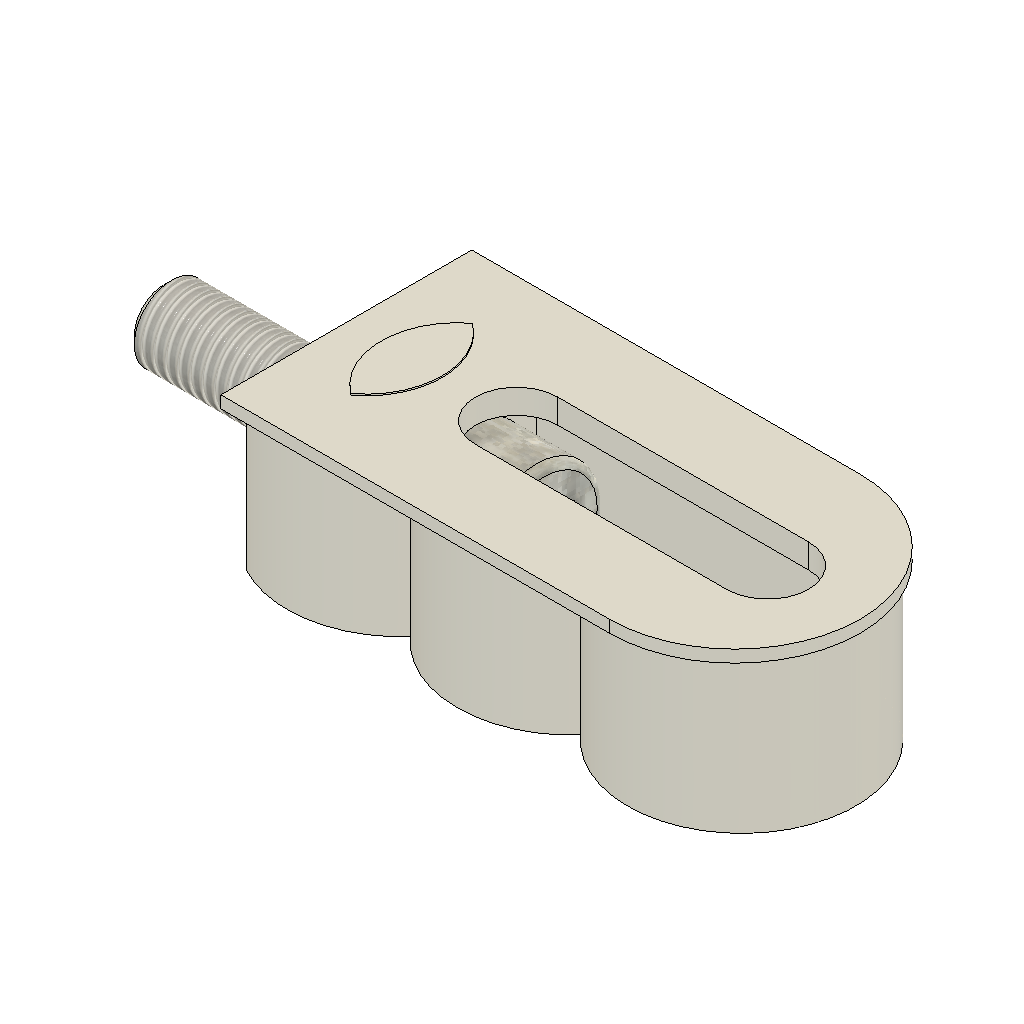
Lamello Cabineo Config (Autodesk Fusion 360 archive; units mm, degrees)
design "Lamello Cabineo Configurable"
description: Lamello Cabineo
part number: Cabineo 12
description: Cap
part number: Lamello Cabineo Cap
description: Lamello Insert
part number: M6 Insert 12.3 mm
Autodesk Fusion 360 part; units mm, degrees
sketch "Sketch1" plane through (0, 0, 0) normal (0, 1, 0) x (1, 0, 0)
  circle A0 centre (14.8, 0) radius 7.5
  circle A1 centre (26, 0) radius 7.5
  line L0 (0, 6.5795) -> (0, -6.5795)
  arc A2 (0, -6.5795) -> (0, 6.5795) centre (3.6, 0) ccw
  dimension "Cabineo_hole_Dia" = 15
  dimension "d9" = 11.2
  dimension "d10" = 11.2
  dimension "d11" = 3.6
  constraint equal A0 A1
  constraint equal A0 A2
  constraint horizontal A2.centre A0.centre
  constraint horizontal A0.centre A1.centre
  constraint vertical L0
  constraint horizontal origin A2.centre
  constraint coincident origin L0
  measures "Cabineo_hole_Dia" diameter of A1
  measures "d9" distance of A0.centre A1.centre
  measures "d10" distance of A2.centre A0.centre
  measures "d11" distance of origin A2.centre
extrude "Extrude1" add sketch "Sketch1" along normal mid plane 10 makes body 1 in component "Lamello Cabineo"
sketch "Sketch1 (2)" plane through (0, 5, 0) normal (0, 1, 0) x (-1, 0, 0) in component "Lamello Cabineo"
  arc A0 (0, 6.5795) -> (-9.2, 4.989) centre (-3.6, 0) ccw
  arc A1 (-9.2, 4.989) -> (-20.4, 4.989) centre (-14.8, 0) ccw
  arc A2 (-20.4, -4.989) -> (-9.2, -4.989) centre (-14.8, 0) ccw
  arc A3 (-9.2, -4.989) -> (0, -6.5795) centre (-3.6, 0) ccw
  line L0 (0, -6.5795) -> (0, 6.5795)
  circle A4 centre (-25.55, 0) radius 8.25
  line L1 (0, -8.25) -> (0, 8.25)
  line L2 (0, 8.25) -> (-25.55, 8.25)
  line L3 (0, -8.25) -> (-25.55, -8.25)
  point P0 (-33.8, 0)
  dimension "d14" = 16.5
  dimension "d74" = 33.8
  constraint vertical L1
  constraint tangent A4 L3
  constraint tangent A4 L2
  constraint coincident A4 L3.end
  constraint coincident A4 L2.end
  constraint collinear L0 L1
  constraint horizontal L3
  constraint horizontal L2
  constraint coincident A4 P0
  constraint horizontal A4.centre P0
  constraint horizontal origin A4.centre
  measures "d14" diameter of A4
  measures "d74" distance of L1 P0
extrude "Extrude2" add sketch "Sketch1 (2)" along normal blind 0.8 bodies 1 in component "Lamello Cabineo"
sketch "Sketch2" plane through (0, 5.8, 0) normal (0, 1, 0) x (-1, 0, 0) in component "Lamello Cabineo"
  line L0 (0, -8.25) -> (0, 8.25)
  line L1 (0, 8.25) -> (-25.55, 8.25)
  arc A0 (-25.55, 8.25) -> (-25.55, -8.25) centre (-25.55, 0) ccw
  line L2 (-25.55, -8.25) -> (0, -8.25)
  arc A1 (-4.3, 4) -> (-4.3, -4) centre (-1.3, 0) ccw
  arc A2 (-4.3, -4) -> (-4.3, 4) centre (-7.3, 0) ccw
  dimension "d17" = 1.3
  dimension "d18" = 7.3
  dimension "d19" = 5
  constraint coincident A1.end A2.start
  constraint coincident A1.start A2.end
  constraint horizontal origin A1.centre
  constraint horizontal origin A2.centre
  constraint equal A1 A2
  measures "d17" distance of L0 A1.centre
  measures "d18" horizontal distance of origin A2.centre
  measures "d19" radius of A1
extrude "Extrude3" add sketch "Sketch2" along normal blind 0.1 contours A1 A2 bodies 1 in component "Lamello Cabineo"
sketch "Sketch3" plane through (0, 5.8, 0) normal (0, 1, 0) x (-1, 0, 0) in component "Lamello Cabineo"
  arc A0 (-4.3, 4) -> (-4.3, -4) centre (-1.3, 0) ccw
  arc A1 (-4.3, -4) -> (-4.3, 4) centre (-7.3, 0) ccw
  line L0 (0, -8.25) -> (0, 8.25)
  line L1 (0, 8.25) -> (-25.55, 8.25)
  arc A2 (-25.55, 8.25) -> (-25.55, -8.25) centre (-25.55, 0) ccw
  line L2 (-25.55, -8.25) -> (0, -8.25)
  line L3 (-11.2, 2.7) -> (-27.7, 2.7)
  arc A3 (-27.7, 2.7) -> (-27.7, -2.7) centre (-27.7, 0) ccw
  line L4 (-27.7, -2.7) -> (-11.2, -2.7)
  arc A4 (-11.2, -2.7) -> (-11.2, 2.7) centre (-11.2, 0) ccw
  line L5 (-11.2, 0) -> (-27.7, 0) construction
  dimension "d22" = 16.5
  dimension "d23" = 11.2
  dimension "d24" = 2.7
  constraint tangent L3 A3
  constraint tangent A3 L4
  constraint parallel L3 L4
  constraint tangent L4 A4
  constraint tangent L3 A4
  constraint horizontal L5
  constraint horizontal origin A4.centre
  measures "d22" distance of A4.centre A3.centre
  measures "d23" horizontal distance of origin A4.centre
  measures "d24" distance of L4 L5
extrude "Extrude4" cut sketch "Sketch3" against normal blind 8 contours L3 A3 L4 A4 bodies 1 in component "Lamello Cabineo"
sketch "Sketch4" plane through (0, 0, 0) normal (-1, 0, 0) x (0, 0, 1) in component "Lamello Cabineo"
  line L0 (6.5795, -5) -> (6.5795, 5)
  line L1 (6.5795, 5) -> (8.25, 5)
  line L2 (8.25, 5) -> (8.25, 5.8)
  line L3 (8.25, 5.8) -> (-8.25, 5.8)
  line L4 (-8.25, 5.8) -> (-8.25, 5)
  line L5 (-8.25, 5) -> (-6.5795, 5)
  line L6 (-6.5795, 5) -> (-6.5795, -5)
  line L7 (-6.5795, -5) -> (6.5795, -5)
  circle A0 centre (0, 0) radius 2.5
  dimension "d27" = 5
  dimension "d29" = 5
  constraint vertical A0.centre origin
  measures "d27" diameter of A0
  measures "d29" vertical distance of L1.end A0.centre
extrude "Extrude5" cut sketch "Sketch4" against normal blind 8 contours A0 bodies 1 in component "Lamello Cabineo"
ref_plane "WorkPlane1" through (11.2, 1.8, 2.7) normal (-1, 0, 0) x (0, -1, 0) in component "Lamello Cabineo"
sketch "Sketch5" plane through (11.2, 0, 0) normal (-1, 0, 0) x (0, 0, 1) in component "Lamello Cabineo"
  circle A0 centre (0, 0) radius 2.5
  line L0 (4.5, -2.2) -> (-4.5, -2.2)
  line L1 (-4.5, -2.2) -> (-4.5, 2.2)
  line L2 (-4.5, 2.2) -> (4.5, 2.2)
  line L3 (4.5, 2.2) -> (4.5, -2.2)
  line L4 (4.5, -2.2) -> (-4.5, 2.2) construction
  line L5 (-4.5, -2.2) -> (4.5, 2.2) construction
  line L6 (4.5, -4.2) -> (-4.5, -4.2)
  line L7 (-4.5, -4.2) -> (-4.5, 4.2)
  line L8 (-4.5, 4.2) -> (4.5, 4.2)
  line L9 (4.5, 4.2) -> (4.5, -4.2)
  line L10 (4.5, -4.2) -> (-4.5, 4.2) construction
  line L11 (-4.5, -4.2) -> (4.5, 4.2) construction
  line L12 (-2.7, -2.2) -> (2.7, -2.2)
  dimension "d33" = 9
  dimension "d34" = 2
  constraint horizontal L0
  constraint perpendicular L0 L1
  constraint parallel L0 L2
  constraint parallel L1 L3
  constraint coincident L4 A0.centre
  constraint coincident L5 A0.centre
  constraint coincident A0.centre origin
  constraint horizontal L6
  constraint perpendicular L6 L7
  constraint parallel L6 L8
  constraint parallel L7 L9
  constraint coincident L10 A0.centre
  constraint coincident L11 A0.centre
  constraint collinear L1 L7
  constraint collinear L0 L12
  measures "d33" distance of L7 L9
  measures "d34" distance of L2 L8
extrude "Extrude6" cut sketch "Sketch5" along normal blind 3.2 and the other way blind 20 bodies 1 in component "Lamello Cabineo"
sketch "Sketch6" plane through (0, 5, 0) normal (0, -1, 0) x (1, 0, 0) in component "Lamello Cabineo"
  arc A0 (0, -6.5795) -> (9.2, -4.989) centre (3.6, 0) ccw
  line L0 (0, -6.5795) -> (0, -8.25)
  line L1 (0, -8.25) -> (25.55, -8.25)
  arc A1 (25.55, -8.25) -> (25.55, 8.25) centre (25.55, 0) ccw
  line L2 (25.55, 8.25) -> (0, 8.25)
  line L3 (0, 8.25) -> (0, 6.5795)
  arc A2 (9.2, 4.989) -> (0, 6.5795) centre (3.6, 0) ccw
  arc A3 (20.4, 4.989) -> (9.2, 4.989) centre (14.8, 0) ccw
  arc A4 (20.4, -4.989) -> (20.4, 4.989) centre (25.55, 0) ccw
  arc A5 (9.2, -4.989) -> (20.4, -4.989) centre (14.8, 0) ccw
  arc A6 (9.2, 4.989) -> (0, 6.5795) centre (3.6, 0) ccw
  line L4 (0, 6.5795) -> (0, -6.5795)
  arc A7 (0, -6.5795) -> (9.2, -4.989) centre (3.6, 0) ccw
  arc A8 (9.2, -4.989) -> (20.4, -4.989) centre (14.8, 0) ccw
  arc A9 (20.4, -4.989) -> (20.4, 4.989) centre (26, 0) ccw
  arc A10 (20.4, 4.989) -> (9.2, 4.989) centre (14.8, 0) ccw
  point P0 (26, 0)
  point P1 (26, 0)
  point P2 (26, 0)
  point P3 (26, 0)
extrude "Extrude7" add sketch "Sketch6" along normal blind 11 and the other way blind 0.001 separate body contours A0 A2 A3 A4 A5 A6 L4 A7 A8 A10 | A4 A9 makes body 2 in component "Lamello Cabineo"
sketch "Sketch7" plane through (0, 5, 0) normal (0, -1, 0) x (1, 0, 0) in component "Lamello Cabineo"
  arc A0 (0, -6.5795) -> (9.2, -4.989) centre (3.6, 0) ccw
  line L0 (0, -6.5795) -> (0, -8.25)
  line L1 (0, -8.25) -> (25.55, -8.25)
  arc A1 (25.55, -8.25) -> (25.55, 8.25) centre (25.55, 0) ccw
  line L2 (25.55, 8.25) -> (0, 8.25)
  line L3 (0, 8.25) -> (0, 6.5795)
  arc A2 (9.2, 4.989) -> (0, 6.5795) centre (3.6, 0) ccw
  arc A3 (20.4, 4.989) -> (9.2, 4.989) centre (14.8, 0) ccw
  arc A4 (20.4, -4.989) -> (20.4, 4.989) centre (25.55, 0) ccw construction
  arc A5 (9.2, -4.989) -> (20.4, -4.989) centre (14.8, 0) ccw
  arc A6 (20.4, -4.989) -> (20.4, 4.989) centre (26, 0) ccw
  circle A7 centre (26, 0) radius 8.35
  line L4 (0, 8.35) -> (0, -8.35)
  line L5 (0, 8.35) -> (26, 8.35)
  line L6 (0, -8.35) -> (26, -8.35)
  point P0 (26, 0)
  point P1 (26, 0)
  point P2 (26, 0)
  point P3 (26, 0)
  point P4 (26, 0)
  dimension "d41" = 16.7
  constraint concentric A6 A7
  constraint vertical L4
  constraint tangent A7 L5
  constraint tangent A7 L6
  constraint coincident origin L4
  constraint coincident A7 L5.end
  constraint coincident A7 L6.end
  constraint horizontal L5
  constraint horizontal L6
  measures "d41" diameter of A7
extrude "Ledge" add sketch "Sketch7" against normal blind 0.801 separate body makes body 3 in component "Lamello Cabineo"
sketch "Sketch2 (2)" plane through (0, 0, 0) normal (0, 0, 1) x (1, 0, 0)
  line L0 (-12, 0) -> (13, 0)
  line L1 (-12, 0) -> (-12, 2.5)
  line L2 (-12, 2.5) -> (8, 2.5)
  line L3 (8, 2.5) -> (8, 4)
  line L4 (8, 4) -> (13, 4)
  line L5 (13, 4) -> (13, 0)
  line L6 (8, -2.5) -> (8, 2.5) construction
  line L7 (0, -5) -> (0, 5) construction
  line L8 (8, 4.2) -> (8, -4.2)
  point P0 (8, 0)
  dimension "d46" = 12
  dimension "d47" = 5
  dimension "d48" = 8
  dimension "d49" = 5
  constraint horizontal L0
  constraint perpendicular L0 L1
  constraint perpendicular L1 L2
  constraint perpendicular L2 L3
  constraint perpendicular L3 L4
  constraint perpendicular L0 L5
  constraint midpoint L6 P0
  constraint coincident L0 P0
  constraint collinear L3 L8
  measures "d46" distance of L1 L7
  measures "d47" distance of L3 L5
revolve "Revolve1" add sketch "Sketch2 (2)" angle 360 about axis through (-12, 0, 0) along (1, 0, 0) separate body makes body 4 in component "Bolt"
chamfer "Chamfer1" distance 0.5 angle 45 1 edges at (-12, -0.904, 2.3308) tangent chain off on bodies 4 in component "Bolt"
fillet "Fillet1" radius 0.5 1 edges at (13, -1.4465, 3.7293) on bodies 4 in component "Bolt"
sketch "Sketch1 (3)" plane through (13, 0, 0) normal (1, 0, 0) x (0, 0, -1) in component "Bolt"
  circle A0 centre (0, 0) radius 3.5
  line L0 (2, 1.1547) -> (0, 2.3094)
  line L1 (0, 2.3094) -> (-2, 1.1547)
  line L2 (-2, 1.1547) -> (-2, -1.1547)
  line L3 (-2, -1.1547) -> (0, -2.3094)
  line L4 (0, -2.3094) -> (2, -1.1547)
  line L5 (2, -1.1547) -> (2, 1.1547)
  dimension "d54" = 4
  constraint coincident A0.centre origin
  constraint vertical L5
  measures "d54" distance of L2 L5
extrude "Extrude1'" cut sketch "Sketch1 (3)" against normal blind 4 contours L0 L1 L2 L3 L4 L5 bodies 4 in component "Bolt"
thread "Thread1" "ISO Metric profile 5.0 M5x0.8 M5x0.8 6g" major diameter 4.901 minor diameter 3.9895 pitch 0.8 angle 60 resizes the face on face at (1.5, 2.4876, -0.2489) on bodies 4 in component "Bolt"
sketch "Sketch2 (3)" plane through (-12, 0, 0) normal (-1, 0, 0) x (0, 0, 1) in component "Bolt"
  circle A0 centre (0, 0) radius 1.9505
  circle A1 centre (0, 0) radius 2.5
  dimension "d59" = 5
  constraint coincident A0.centre A1.centre
  measures "d59" diameter of A1
extrude "Extrude2'" add sketch "Sketch2 (3)" against normal blind 12.001 separate body contours A0 | A1 makes body 5 in component "Bolt"
sketch "Sketch1 (4)" plane through (0, 0, 0) normal (0, 1, 0) x (1, 0, 0) in component "Lamello Cabineo Cap v2"
  circle A0 centre (25.96, 0) radius 9.25
  line L0 (0, 9.25) -> (0, -9.25)
  line L1 (0, 9.25) -> (25.96, 9.25)
  line L2 (0, -9.25) -> (25.96, -9.25)
  dimension "d1" = 18.5
  dimension "d2" = 25.96
  constraint vertical L0
  constraint horizontal origin A0.centre
  constraint tangent A0 L1
  constraint tangent A0 L2
  constraint horizontal L2
  constraint coincident A0 L1.end
  constraint coincident A0 L2.end
  constraint horizontal L1
  constraint coincident origin L0
  measures "d1" diameter of A0
  measures "d2" distance of A0.centre L0
extrude "Extrude1''" [suppressed] in component "Lamello Cabineo Cap v2"
shell "Shell1" [suppressed] in component "Lamello Cabineo Cap v2"
fillet "Fillet1'" [suppressed] in component "Lamello Cabineo Cap v2"
fillet "Fillet2" [suppressed] in component "Lamello Cabineo Cap v2"
sketch "Sketch2 (4)" plane through (0, 1, 0) normal (0, -1, 0) x (1, 0, 0) in component "Lamello Cabineo Cap v2"
  line L0 (0, 8.25) -> (0, -8.25)
  line L1 (0, 0) -> (30, 0)
  line L2 (11.2, 2.7) -> (27.7, 2.7)
  line L3 (27.7, 2.7) -> (27.7, 2.2)
  line L4 (27.7, 2.2) -> (11.2, 2.2)
  line L5 (11.2, 2.2) -> (11.2, 2.7)
  line L6 (11.2, -2.7) -> (27.7, -2.7)
  line L7 (27.7, -2.7) -> (27.7, -2.2)
  line L8 (27.7, -2.2) -> (11.2, -2.2)
  line L9 (11.2, -2.2) -> (11.2, -2.7)
  line L10 (0, -8.25) -> (25.96, -8.25)
  arc A0 (25.96, -8.25) -> (25.96, 8.25) centre (25.96, 0) ccw
  line L11 (25.96, 8.25) -> (0, 8.25)
  dimension "d10_1" = 0.5
  dimension "d11_1" = 16.5
  dimension "d12_1" = 11.2
  dimension "d13_1" = 5.4
  dimension "d14_1" = 0.5
  dimension "d15_1" = 5.4
  constraint coincident L1.start origin
  constraint perpendicular L0 L1
  constraint horizontal L2
  constraint vertical L3
  constraint horizontal L4
  constraint vertical L5
  constraint horizontal L6
  constraint vertical L7
  constraint horizontal L8
  constraint vertical L9
  constraint vertical L4.end L8.end
  constraint vertical L3.end L7.end
  measures "d10_1" distance of L2.start L4.end
  measures "d11_1" distance of L3.end L4.end
  measures "d12_1" distance of L0 L4.end
  measures "d14_1" distance of L6.start L8.end
extrude "Extrude2''" [suppressed] in component "Lamello Cabineo Cap v2"
chamfer "Chamfer1'" [suppressed] in component "Lamello Cabineo Cap v2"
imported_body "Base Feature1" makes body 7 makes body 8 in component "M6 Insert v2"
sketch "Coord_Y" plane through (0, 0, 0) normal (-1, 0, 0) x (0, 0, 1)
  circle A0 centre (0, 0) radius 2.5
  line L0 (6.5795, -5) -> (6.5795, 5)
  line L1 (6.5795, 5) -> (8.25, 5)
  line L2 (8.25, 5) -> (8.25, 5.8)
  line L3 (8.25, 5.8) -> (-8.25, 5.8)
  line L4 (-8.25, 5.8) -> (-8.25, 5)
  line L5 (-8.25, 5) -> (-6.5795, 5)
  line L6 (-6.5795, 5) -> (-6.5795, -5)
  line L7 (-6.5795, -5) -> (6.5795, -5)
  point P0 (0, 5)
  dimension "d72" = 5
  constraint vertical A0.centre P0
  measures "d72" vertical distance of A0.centre P0
component "Lamello Cabineo" placed x (1, 0, 0) y (0, 1, 0) z (0, 0, 1) at (0, 0, 0)
component "Bolt" placed x (1, 0, 0) y (0, 1, 0) z (0, 0, 1) at (0, 0, 0)
hidden bodies 2 3 5
equation "Hole_D = 5 mm"
equation "Ledge_Size = 0.8 mm"
equation "Drilling_depth = 11 mm"
equation "Ledge_dia = 16.7 mm"
equation "Dist_from_edge = 3.6 mm"
equation "Outside_L = 12 mm"
equation "Bolt_L = Outside_L + 8 mm"
equation "d11 = Dist_from_edge"
equation "d27 = Hole_D"
equation "d39 = Drilling_depth"
equation "d41 = Ledge_dia"
equation "d42 = -Ledge_Size - 0.001 mm"
equation "d46 = Outside_L"
equation "d59 = Hole_D"
equation "d60 = -Outside_L - 0.001 mm"
equation "d15_1 = d13_1"
equation "Coord_Y = 5 mm"
equation "d72 = Coord_Y"
equation "Code = 'Cabineo 12'"
named bodies: "Cabineo body", "Cabineo hole", "Legde hole", "Bolt", "Bolt Hole", "Insert M6", "Hole"

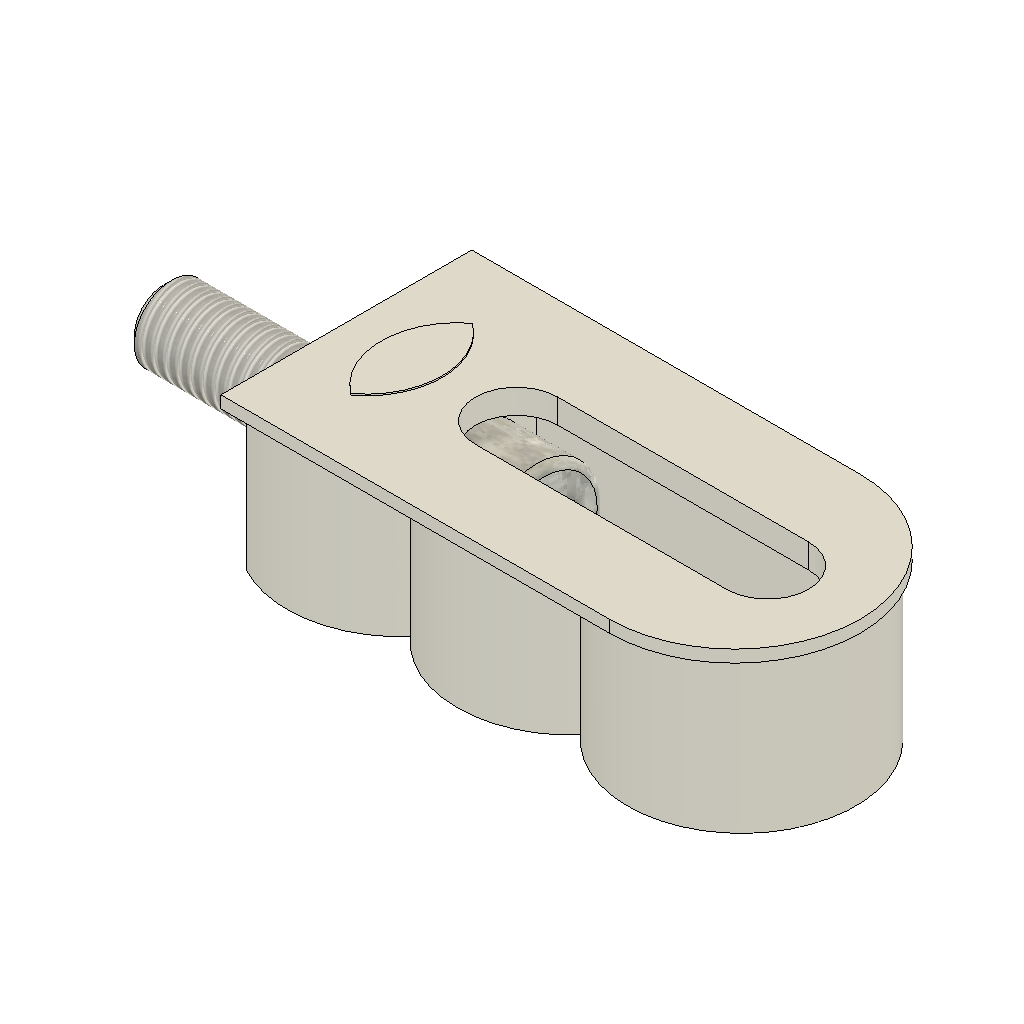
design "Cabineo 12 On the surface"
description: Lamello Cabineo
part number: Cabineo 12
description: Cap
part number: Lamello Cabineo Cap
description: Lamello Insert
part number: M6 Insert 12.3 mm
Autodesk Fusion 360 part; units mm, degrees
sketch "Sketch1" plane through (0, 0, 0) normal (0, 1, 0) x (1, 0, 0)
  circle A0 centre (14.8, 0) radius 7.5
  circle A1 centre (26, 0) radius 7.5
  line L0 (0, 6.5795) -> (0, -6.5795)
  arc A2 (0, -6.5795) -> (0, 6.5795) centre (3.6, 0) ccw
  dimension "Cabineo_hole_Dia" = 15
  dimension "d9" = 11.2
  dimension "d10" = 11.2
  dimension "d11" = 3.6
  constraint equal A0 A1
  constraint equal A0 A2
  constraint horizontal A2.centre A0.centre
  constraint horizontal A0.centre A1.centre
  constraint vertical L0
  constraint horizontal origin A2.centre
  constraint coincident origin L0
  measures "Cabineo_hole_Dia" diameter of A1
  measures "d9" distance of A0.centre A1.centre
  measures "d10" distance of A2.centre A0.centre
  measures "d11" distance of origin A2.centre
extrude "Extrude1" add sketch "Sketch1" along normal mid plane 10 makes body 1 in component "Lamello Cabineo"
sketch "Sketch1 (2)" plane through (0, 5, 0) normal (0, 1, 0) x (-1, 0, 0) in component "Lamello Cabineo"
  arc A0 (0, 6.5795) -> (-9.2, 4.989) centre (-3.6, 0) ccw
  arc A1 (-9.2, 4.989) -> (-20.4, 4.989) centre (-14.8, 0) ccw
  arc A2 (-20.4, -4.989) -> (-9.2, -4.989) centre (-14.8, 0) ccw
  arc A3 (-9.2, -4.989) -> (0, -6.5795) centre (-3.6, 0) ccw
  line L0 (0, -6.5795) -> (0, 6.5795)
  circle A4 centre (-25.55, 0) radius 8.25
  line L1 (0, -8.25) -> (0, 8.25)
  line L2 (0, 8.25) -> (-25.55, 8.25)
  line L3 (0, -8.25) -> (-25.55, -8.25)
  point P0 (-33.8, 0)
  dimension "d14" = 16.5
  dimension "d74" = 33.8
  constraint vertical L1
  constraint tangent A4 L3
  constraint tangent A4 L2
  constraint coincident A4 L3.end
  constraint coincident A4 L2.end
  constraint collinear L0 L1
  constraint horizontal L3
  constraint horizontal L2
  constraint coincident A4 P0
  constraint horizontal A4.centre P0
  constraint horizontal origin A4.centre
  measures "d14" diameter of A4
  measures "d74" distance of L1 P0
extrude "Extrude2" add sketch "Sketch1 (2)" along normal blind 0.8 bodies 1 in component "Lamello Cabineo"
sketch "Sketch2" plane through (0, 5.8, 0) normal (0, 1, 0) x (-1, 0, 0) in component "Lamello Cabineo"
  line L0 (0, -8.25) -> (0, 8.25)
  line L1 (0, 8.25) -> (-25.55, 8.25)
  arc A0 (-25.55, 8.25) -> (-25.55, -8.25) centre (-25.55, 0) ccw
  line L2 (-25.55, -8.25) -> (0, -8.25)
  arc A1 (-4.3, 4) -> (-4.3, -4) centre (-1.3, 0) ccw
  arc A2 (-4.3, -4) -> (-4.3, 4) centre (-7.3, 0) ccw
  dimension "d17" = 1.3
  dimension "d18" = 7.3
  dimension "d19" = 5
  constraint coincident A1.end A2.start
  constraint coincident A1.start A2.end
  constraint horizontal origin A1.centre
  constraint horizontal origin A2.centre
  constraint equal A1 A2
  measures "d17" distance of L0 A1.centre
  measures "d18" horizontal distance of origin A2.centre
  measures "d19" radius of A1
extrude "Extrude3" add sketch "Sketch2" along normal blind 0.1 contours A1 A2 bodies 1 in component "Lamello Cabineo"
sketch "Sketch3" plane through (0, 5.8, 0) normal (0, 1, 0) x (-1, 0, 0) in component "Lamello Cabineo"
  arc A0 (-4.3, 4) -> (-4.3, -4) centre (-1.3, 0) ccw
  arc A1 (-4.3, -4) -> (-4.3, 4) centre (-7.3, 0) ccw
  line L0 (0, -8.25) -> (0, 8.25)
  line L1 (0, 8.25) -> (-25.55, 8.25)
  arc A2 (-25.55, 8.25) -> (-25.55, -8.25) centre (-25.55, 0) ccw
  line L2 (-25.55, -8.25) -> (0, -8.25)
  line L3 (-11.2, 2.7) -> (-27.7, 2.7)
  arc A3 (-27.7, 2.7) -> (-27.7, -2.7) centre (-27.7, 0) ccw
  line L4 (-27.7, -2.7) -> (-11.2, -2.7)
  arc A4 (-11.2, -2.7) -> (-11.2, 2.7) centre (-11.2, 0) ccw
  line L5 (-11.2, 0) -> (-27.7, 0) construction
  dimension "d22" = 16.5
  dimension "d23" = 11.2
  dimension "d24" = 2.7
  constraint tangent L3 A3
  constraint tangent A3 L4
  constraint parallel L3 L4
  constraint tangent L4 A4
  constraint tangent L3 A4
  constraint horizontal L5
  constraint horizontal origin A4.centre
  measures "d22" distance of A4.centre A3.centre
  measures "d23" horizontal distance of origin A4.centre
  measures "d24" distance of L4 L5
extrude "Extrude4" cut sketch "Sketch3" against normal blind 8 contours L3 A3 L4 A4 bodies 1 in component "Lamello Cabineo"
sketch "Sketch4" plane through (0, 0, 0) normal (-1, 0, 0) x (0, 0, 1) in component "Lamello Cabineo"
  line L0 (6.5795, -5) -> (6.5795, 5)
  line L1 (6.5795, 5) -> (8.25, 5)
  line L2 (8.25, 5) -> (8.25, 5.8)
  line L3 (8.25, 5.8) -> (-8.25, 5.8)
  line L4 (-8.25, 5.8) -> (-8.25, 5)
  line L5 (-8.25, 5) -> (-6.5795, 5)
  line L6 (-6.5795, 5) -> (-6.5795, -5)
  line L7 (-6.5795, -5) -> (6.5795, -5)
  circle A0 centre (0, 0) radius 2.5
  dimension "d27" = 5
  dimension "d29" = 5
  constraint vertical A0.centre origin
  measures "d27" diameter of A0
  measures "d29" vertical distance of L1.end A0.centre
extrude "Extrude5" cut sketch "Sketch4" against normal blind 8 contours A0 bodies 1 in component "Lamello Cabineo"
ref_plane "WorkPlane1" through (11.2, 1.8, 2.7) normal (-1, 0, 0) x (0, -1, 0) in component "Lamello Cabineo"
sketch "Sketch5" plane through (11.2, 0, 0) normal (-1, 0, 0) x (0, 0, 1) in component "Lamello Cabineo"
  circle A0 centre (0, 0) radius 2.5
  line L0 (4.5, -2.2) -> (-4.5, -2.2)
  line L1 (-4.5, -2.2) -> (-4.5, 2.2)
  line L2 (-4.5, 2.2) -> (4.5, 2.2)
  line L3 (4.5, 2.2) -> (4.5, -2.2)
  line L4 (4.5, -2.2) -> (-4.5, 2.2) construction
  line L5 (-4.5, -2.2) -> (4.5, 2.2) construction
  line L6 (4.5, -4.2) -> (-4.5, -4.2)
  line L7 (-4.5, -4.2) -> (-4.5, 4.2)
  line L8 (-4.5, 4.2) -> (4.5, 4.2)
  line L9 (4.5, 4.2) -> (4.5, -4.2)
  line L10 (4.5, -4.2) -> (-4.5, 4.2) construction
  line L11 (-4.5, -4.2) -> (4.5, 4.2) construction
  line L12 (-2.7, -2.2) -> (2.7, -2.2)
  dimension "d33" = 9
  dimension "d34" = 2
  constraint horizontal L0
  constraint perpendicular L0 L1
  constraint parallel L0 L2
  constraint parallel L1 L3
  constraint coincident L4 A0.centre
  constraint coincident L5 A0.centre
  constraint coincident A0.centre origin
  constraint horizontal L6
  constraint perpendicular L6 L7
  constraint parallel L6 L8
  constraint parallel L7 L9
  constraint coincident L10 A0.centre
  constraint coincident L11 A0.centre
  constraint collinear L1 L7
  constraint collinear L0 L12
  measures "d33" distance of L7 L9
  measures "d34" distance of L2 L8
extrude "Extrude6" cut sketch "Sketch5" along normal blind 3.2 and the other way blind 20 bodies 1 in component "Lamello Cabineo"
sketch "Sketch6" plane through (0, 5, 0) normal (0, -1, 0) x (1, 0, 0) in component "Lamello Cabineo"
  arc A0 (0, -6.5795) -> (9.2, -4.989) centre (3.6, 0) ccw
  line L0 (0, -6.5795) -> (0, -8.25)
  line L1 (0, -8.25) -> (25.55, -8.25)
  arc A1 (25.55, -8.25) -> (25.55, 8.25) centre (25.55, 0) ccw
  line L2 (25.55, 8.25) -> (0, 8.25)
  line L3 (0, 8.25) -> (0, 6.5795)
  arc A2 (9.2, 4.989) -> (0, 6.5795) centre (3.6, 0) ccw
  arc A3 (20.4, 4.989) -> (9.2, 4.989) centre (14.8, 0) ccw
  arc A4 (20.4, -4.989) -> (20.4, 4.989) centre (25.55, 0) ccw
  arc A5 (9.2, -4.989) -> (20.4, -4.989) centre (14.8, 0) ccw
  arc A6 (9.2, 4.989) -> (0, 6.5795) centre (3.6, 0) ccw
  line L4 (0, 6.5795) -> (0, -6.5795)
  arc A7 (0, -6.5795) -> (9.2, -4.989) centre (3.6, 0) ccw
  arc A8 (9.2, -4.989) -> (20.4, -4.989) centre (14.8, 0) ccw
  arc A9 (20.4, -4.989) -> (20.4, 4.989) centre (26, 0) ccw
  arc A10 (20.4, 4.989) -> (9.2, 4.989) centre (14.8, 0) ccw
  point P0 (26, 0)
  point P1 (26, 0)
  point P2 (26, 0)
  point P3 (26, 0)
extrude "Extrude7" add sketch "Sketch6" along normal blind 11 and the other way blind 0.001 separate body contours A0 A2 A3 A4 A5 A6 L4 A7 A8 A10 | A4 A9 makes body 2 in component "Lamello Cabineo"
sketch "Sketch7" plane through (0, 5, 0) normal (0, -1, 0) x (1, 0, 0) in component "Lamello Cabineo"
  arc A0 (0, -6.5795) -> (9.2, -4.989) centre (3.6, 0) ccw
  line L0 (0, -6.5795) -> (0, -8.25)
  line L1 (0, -8.25) -> (25.55, -8.25)
  arc A1 (25.55, -8.25) -> (25.55, 8.25) centre (25.55, 0) ccw
  line L2 (25.55, 8.25) -> (0, 8.25)
  line L3 (0, 8.25) -> (0, 6.5795)
  arc A2 (9.2, 4.989) -> (0, 6.5795) centre (3.6, 0) ccw
  arc A3 (20.4, 4.989) -> (9.2, 4.989) centre (14.8, 0) ccw
  arc A4 (20.4, -4.989) -> (20.4, 4.989) centre (25.55, 0) ccw construction
  arc A5 (9.2, -4.989) -> (20.4, -4.989) centre (14.8, 0) ccw
  arc A6 (20.4, -4.989) -> (20.4, 4.989) centre (26, 0) ccw
  circle A7 centre (26, 0) radius 8.35
  line L4 (0, 8.35) -> (0, -8.35)
  line L5 (0, 8.35) -> (26, 8.35)
  line L6 (0, -8.35) -> (26, -8.35)
  point P0 (26, 0)
  point P1 (26, 0)
  point P2 (26, 0)
  point P3 (26, 0)
  point P4 (26, 0)
  dimension "d41" = 16.7
  constraint concentric A6 A7
  constraint vertical L4
  constraint tangent A7 L5
  constraint tangent A7 L6
  constraint coincident origin L4
  constraint coincident A7 L5.end
  constraint coincident A7 L6.end
  constraint horizontal L5
  constraint horizontal L6
  measures "d41" diameter of A7
extrude "Ledge" add sketch "Sketch7" against normal blind 0.801 separate body makes body 3 in component "Lamello Cabineo"
sketch "Sketch2 (2)" plane through (0, 0, 0) normal (0, 0, 1) x (1, 0, 0)
  line L0 (-12, 0) -> (13, 0)
  line L1 (-12, 0) -> (-12, 2.5)
  line L2 (-12, 2.5) -> (8, 2.5)
  line L3 (8, 2.5) -> (8, 4)
  line L4 (8, 4) -> (13, 4)
  line L5 (13, 4) -> (13, 0)
  line L6 (8, -2.5) -> (8, 2.5) construction
  line L7 (0, -5) -> (0, 5) construction
  line L8 (8, 4.2) -> (8, -4.2)
  point P0 (8, 0)
  dimension "d46" = 12
  dimension "d47" = 5
  dimension "d48" = 8
  dimension "d49" = 5
  constraint horizontal L0
  constraint perpendicular L0 L1
  constraint perpendicular L1 L2
  constraint perpendicular L2 L3
  constraint perpendicular L3 L4
  constraint perpendicular L0 L5
  constraint midpoint L6 P0
  constraint coincident L0 P0
  constraint collinear L3 L8
  measures "d46" distance of L1 L7
  measures "d47" distance of L3 L5
revolve "Revolve1" add sketch "Sketch2 (2)" angle 360 about axis through (-12, 0, 0) along (1, 0, 0) separate body makes body 4 in component "Bolt"
chamfer "Chamfer1" distance 0.5 angle 45 1 edges at (-12, -0.904, 2.3308) tangent chain off on bodies 4 in component "Bolt"
fillet "Fillet1" radius 0.5 1 edges at (13, -1.4465, 3.7293) on bodies 4 in component "Bolt"
sketch "Sketch1 (3)" plane through (13, 0, 0) normal (1, 0, 0) x (0, 0, -1) in component "Bolt"
  circle A0 centre (0, 0) radius 3.5
  line L0 (2, 1.1547) -> (0, 2.3094)
  line L1 (0, 2.3094) -> (-2, 1.1547)
  line L2 (-2, 1.1547) -> (-2, -1.1547)
  line L3 (-2, -1.1547) -> (0, -2.3094)
  line L4 (0, -2.3094) -> (2, -1.1547)
  line L5 (2, -1.1547) -> (2, 1.1547)
  dimension "d54" = 4
  constraint coincident A0.centre origin
  constraint vertical L5
  measures "d54" distance of L2 L5
extrude "Extrude1'" cut sketch "Sketch1 (3)" against normal blind 4 contours L0 L1 L2 L3 L4 L5 bodies 4 in component "Bolt"
thread "Thread1" "ISO Metric profile 5.0 M5x0.8 M5x0.8 6g" major diameter 4.901 minor diameter 3.9895 pitch 0.8 angle 60 resizes the face on face at (1.5, 2.4876, -0.2489) on bodies 4 in component "Bolt"
sketch "Sketch2 (3)" plane through (-12, 0, 0) normal (-1, 0, 0) x (0, 0, 1) in component "Bolt"
  circle A0 centre (0, 0) radius 1.9505
  circle A1 centre (0, 0) radius 2.5
  dimension "d59" = 5
  constraint coincident A0.centre A1.centre
  measures "d59" diameter of A1
extrude "Extrude2'" add sketch "Sketch2 (3)" against normal blind 12.001 separate body contours A0 | A1 makes body 5 in component "Bolt"
sketch "Sketch1 (4)" plane through (0, 0, 0) normal (0, 1, 0) x (1, 0, 0) in component "Lamello Cabineo Cap v2"
  circle A0 centre (25.96, 0) radius 9.25
  line L0 (0, 9.25) -> (0, -9.25)
  line L1 (0, 9.25) -> (25.96, 9.25)
  line L2 (0, -9.25) -> (25.96, -9.25)
  dimension "d1" = 18.5
  dimension "d2" = 25.96
  constraint vertical L0
  constraint horizontal origin A0.centre
  constraint tangent A0 L1
  constraint tangent A0 L2
  constraint horizontal L2
  constraint coincident A0 L1.end
  constraint coincident A0 L2.end
  constraint horizontal L1
  constraint coincident origin L0
  measures "d1" diameter of A0
  measures "d2" distance of A0.centre L0
extrude "Extrude1''" [suppressed] in component "Lamello Cabineo Cap v2"
shell "Shell1" [suppressed] in component "Lamello Cabineo Cap v2"
fillet "Fillet1'" [suppressed] in component "Lamello Cabineo Cap v2"
fillet "Fillet2" [suppressed] in component "Lamello Cabineo Cap v2"
sketch "Sketch2 (4)" plane through (0, 1, 0) normal (0, -1, 0) x (1, 0, 0) in component "Lamello Cabineo Cap v2"
  line L0 (0, 8.25) -> (0, -8.25)
  line L1 (0, 0) -> (30, 0)
  line L2 (11.2, 2.7) -> (27.7, 2.7)
  line L3 (27.7, 2.7) -> (27.7, 2.2)
  line L4 (27.7, 2.2) -> (11.2, 2.2)
  line L5 (11.2, 2.2) -> (11.2, 2.7)
  line L6 (11.2, -2.7) -> (27.7, -2.7)
  line L7 (27.7, -2.7) -> (27.7, -2.2)
  line L8 (27.7, -2.2) -> (11.2, -2.2)
  line L9 (11.2, -2.2) -> (11.2, -2.7)
  line L10 (0, -8.25) -> (25.96, -8.25)
  arc A0 (25.96, -8.25) -> (25.96, 8.25) centre (25.96, 0) ccw
  line L11 (25.96, 8.25) -> (0, 8.25)
  dimension "d10_1" = 0.5
  dimension "d11_1" = 16.5
  dimension "d12_1" = 11.2
  dimension "d13_1" = 5.4
  dimension "d14_1" = 0.5
  dimension "d15_1" = 5.4
  constraint coincident L1.start origin
  constraint perpendicular L0 L1
  constraint horizontal L2
  constraint vertical L3
  constraint horizontal L4
  constraint vertical L5
  constraint horizontal L6
  constraint vertical L7
  constraint horizontal L8
  constraint vertical L9
  constraint vertical L4.end L8.end
  constraint vertical L3.end L7.end
  measures "d10_1" distance of L2.start L4.end
  measures "d11_1" distance of L3.end L4.end
  measures "d12_1" distance of L0 L4.end
  measures "d14_1" distance of L6.start L8.end
extrude "Extrude2''" [suppressed] in component "Lamello Cabineo Cap v2"
chamfer "Chamfer1'" [suppressed] in component "Lamello Cabineo Cap v2"
imported_body "Base Feature1" makes body 7 makes body 8 in component "M6 Insert v2"
sketch "Coord_Y" plane through (0, 0, 0) normal (-1, 0, 0) x (0, 0, 1)
  circle A0 centre (0, 0) radius 2.5
  line L0 (6.5795, -5) -> (6.5795, 5)
  line L1 (6.5795, 5) -> (8.25, 5)
  line L2 (8.25, 5) -> (8.25, 5.8)
  line L3 (8.25, 5.8) -> (-8.25, 5.8)
  line L4 (-8.25, 5.8) -> (-8.25, 5)
  line L5 (-8.25, 5) -> (-6.5795, 5)
  line L6 (-6.5795, 5) -> (-6.5795, -5)
  line L7 (-6.5795, -5) -> (6.5795, -5)
  point P0 (0, 5)
  dimension "d72" = 5
  constraint vertical A0.centre P0
  measures "d72" vertical distance of A0.centre P0
component "Lamello Cabineo" placed x (1, 0, 0) y (0, 1, 0) z (0, 0, 1) at (0, 0, 0)
component "Bolt" placed x (1, 0, 0) y (0, 1, 0) z (0, 0, 1) at (0, 0, 0)
hidden bodies 2 3 5
equation "Hole_D = 5 mm"
equation "Ledge_Size = 0.8 mm"
equation "Drilling_depth = 11 mm"
equation "Ledge_dia = 16.7 mm"
equation "Dist_from_edge = 3.6 mm"
equation "Outside_L = 12 mm"
equation "Bolt_L = Outside_L + 8 mm"
equation "d11 = Dist_from_edge"
equation "d27 = Hole_D"
equation "d39 = Drilling_depth"
equation "d41 = Ledge_dia"
equation "d42 = -Ledge_Size - 0.001 mm"
equation "d46 = Outside_L"
equation "d59 = Hole_D"
equation "d60 = -Outside_L - 0.001 mm"
equation "d15_1 = d13_1"
equation "Coord_Y = 5 mm"
equation "d72 = Coord_Y"
equation "Code = 'Cabineo 12'"
named bodies: "Cabineo body", "Cabineo hole", "Legde hole", "Bolt", "Bolt Hole", "Insert M6", "Hole"
